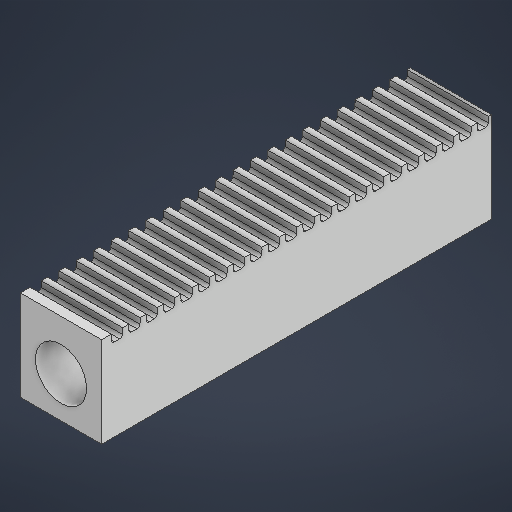
# Autodesk Inventor part: Servo gear pin
Saved by Autodesk Inventor 2027 (Build 310192060, 192F)
## iProperties
Created: 2026-10-23
Part Number: Servo gear pin
Material: Generic
Document SubType Name: Modeling
Designer: troop
Density: 1 g/cm^3
Appearance: Default
Author: troop
Autodesk Inventor part; units mm, degrees
ref_plane "YZ Plane" through (0, 0, 0) normal (1, 0, 0) x (0, 1, 0)
ref_plane "XZ Plane" through (0, 0, 0) normal (0, 1, 0) x (-1, 0, 0)
ref_plane "XY Plane" through (0, 0, 0) normal (0, 0, 1) x (1, 0, 0)
sketch "Sketch1" plane through (0, 0, 0) normal (0, 0, 1) x (1, 0, 0)
  line L0 (0, 0) -> (7.9375, 0)
  line L1 (7.9375, 0) -> (7.9375, 7.9375)
  line L2 (7.9375, 7.9375) -> (0, 7.9375)
  line L3 (0, 7.9375) -> (0, 0)
  dimension "d0" = 7.9375
  dimension "d1" = 7.9375
  constraints: 8 end point, 2 parallel, 1 horizontal, 1 perpendicular
  measures "d0" distance of L2.end L1.end
  measures "d1" distance between parallel lines of L0 L2
extrude "Extrusion1" add sketch "Sketch1" along normal blind 38.1
sketch "Sketch2" plane through (0, 0, 38.1) normal (0, 0, 1) x (1, 0, 0)
  circle A0 centre (3.9688, 3.9688) radius 2.5
  point P0 (0, 0)
  dimension "d4" = 5
  dimension "d5" = 3.9688
  dimension "d6" = 3.9688
  constraints: 1 centre point
  measures "d4" diameter of A0
  measures "d5" horizontal distance of point (0, 0) A0.centre
  measures "d6" horizontal distance of point (0, 0) A0.centre
extrude "Extrusion2" cut sketch "Sketch2" against normal blind 25.4
sketch "Sketch3" plane through (7.9375, 0, 0) normal (1, 0, 0) x (0, 0, -1)
  line L0 (0, 7.9375) -> (-38.1, 7.9375) projected
  line L1 (0, 7.9375) -> (0, 8.8375)
  line L2 (0, 8.8375) -> (-0.3048, 8.8375)
  line L3 (-1.347, 8.0375) -> (-0.347, 8.0375)
  arc A0 (-0.347, 8.0375) -> (-0.3048, 8.8375) centre (-3.3369, 8.5963) ccw
  arc A1 (-1.3978, 8.8375) -> (-1.347, 8.0375) centre (1.6367, 8.6286) ccw
  line L4 (-1.3978, 8.8375) -> (-1.7026, 8.8375)
  line L5 (-1.7026, 8.8375) -> (-1.7026, 7.9375)
  line L6 (-3.4052, 7.9375) -> (-3.4052, 8.8375)
  line L7 (-3.4052, 8.8375) -> (-3.1004, 8.8375)
  line L8 (-2.0582, 8.0375) -> (-3.0582, 8.0375)
  arc A2 (-3.1004, 8.8375) -> (-3.0582, 8.0375) centre (-0.0683, 8.5963) ccw
  arc A3 (-2.0582, 8.0375) -> (-2.0074, 8.8375) centre (-5.0419, 8.6286) ccw
  line L9 (-2.0074, 8.8375) -> (-1.7026, 8.8375)
  line L10 (-6.8104, 7.9375) -> (-6.8104, 8.8375)
  line L11 (-6.8104, 8.8375) -> (-6.5056, 8.8375)
  line L12 (-5.4634, 8.0375) -> (-6.4634, 8.0375)
  arc A4 (-6.5056, 8.8375) -> (-6.4634, 8.0375) centre (-3.4735, 8.5963) ccw
  arc A5 (-5.4634, 8.0375) -> (-5.4126, 8.8375) centre (-8.4471, 8.6286) ccw
  line L13 (-5.4126, 8.8375) -> (-5.1078, 8.8375)
  line L14 (-5.1078, 8.8375) -> (-5.1078, 7.9375)
  line L15 (-3.4052, 8.8375) -> (-3.71, 8.8375)
  line L16 (-4.7522, 8.0375) -> (-3.7522, 8.0375)
  arc A6 (-3.7522, 8.0375) -> (-3.71, 8.8375) centre (-6.7421, 8.5963) ccw
  arc A7 (-4.803, 8.8375) -> (-4.7522, 8.0375) centre (-1.7685, 8.6286) ccw
  line L17 (-4.803, 8.8375) -> (-5.1078, 8.8375)
  line L18 (-13.6207, 7.9375) -> (-13.6207, 8.8375)
  line L19 (-13.6207, 8.8375) -> (-13.3159, 8.8375)
  line L20 (-12.2738, 8.0375) -> (-13.2738, 8.0375)
  arc A8 (-13.3159, 8.8375) -> (-13.2738, 8.0375) centre (-10.2838, 8.5963) ccw
  arc A9 (-12.2738, 8.0375) -> (-12.223, 8.8375) centre (-15.2575, 8.6286) ccw
  line L21 (-12.223, 8.8375) -> (-11.9182, 8.8375)
  line L22 (-11.9182, 8.8375) -> (-11.9182, 7.9375)
  line L23 (-10.2156, 7.9375) -> (-10.2156, 8.8375)
  line L24 (-10.2156, 8.8375) -> (-10.5204, 8.8375)
  line L25 (-11.5626, 8.0375) -> (-10.5626, 8.0375)
  arc A10 (-10.5626, 8.0375) -> (-10.5204, 8.8375) centre (-13.5525, 8.5963) ccw
  arc A11 (-11.6134, 8.8375) -> (-11.5626, 8.0375) centre (-8.5789, 8.6286) ccw
  line L26 (-11.6134, 8.8375) -> (-11.9182, 8.8375)
  line L27 (-8.2082, 8.8375) -> (-8.513, 8.8375)
  arc A12 (-8.2082, 8.8375) -> (-8.1574, 8.0375) centre (-5.1737, 8.6286) ccw
  line L28 (-8.1574, 8.0375) -> (-7.1574, 8.0375)
  arc A13 (-7.1574, 8.0375) -> (-7.1152, 8.8375) centre (-10.1473, 8.5963) ccw
  line L29 (-6.8104, 8.8375) -> (-7.1152, 8.8375)
  line L30 (-8.513, 8.8375) -> (-8.513, 7.9375)
  arc A14 (-8.8686, 8.0375) -> (-8.8178, 8.8375) centre (-11.8523, 8.6286) ccw
  line L31 (-8.8686, 8.0375) -> (-9.8686, 8.0375)
  arc A15 (-9.9108, 8.8375) -> (-9.8686, 8.0375) centre (-6.8787, 8.5963) ccw
  line L32 (-10.2156, 8.8375) -> (-9.9108, 8.8375)
  line L33 (-8.8178, 8.8375) -> (-8.513, 8.8375)
  line L34 (-27.2415, 7.9375) -> (-27.2415, 8.8375)
  line L35 (-27.2415, 8.8375) -> (-26.9367, 8.8375)
  line L36 (-25.8945, 8.0375) -> (-26.8945, 8.0375)
  arc A16 (-26.9367, 8.8375) -> (-26.8945, 8.0375) centre (-23.9046, 8.5963) ccw
  arc A17 (-25.8945, 8.0375) -> (-25.8437, 8.8375) centre (-28.8782, 8.6286) ccw
  line L37 (-25.8437, 8.8375) -> (-25.5389, 8.8375)
  line L38 (-25.5389, 8.8375) -> (-25.5389, 7.9375)
  line L39 (-23.8363, 7.9375) -> (-23.8363, 8.8375)
  line L40 (-23.8363, 8.8375) -> (-24.1411, 8.8375)
  line L41 (-25.1833, 8.0375) -> (-24.1833, 8.0375)
  arc A18 (-24.1833, 8.0375) -> (-24.1411, 8.8375) centre (-27.1732, 8.5963) ccw
  arc A19 (-25.2341, 8.8375) -> (-25.1833, 8.0375) centre (-22.1996, 8.6286) ccw
  line L42 (-25.2341, 8.8375) -> (-25.5389, 8.8375)
  line L43 (-21.8289, 8.8375) -> (-22.1337, 8.8375)
  arc A20 (-21.8289, 8.8375) -> (-21.7781, 8.0375) centre (-18.7944, 8.6286) ccw
  line L44 (-21.7781, 8.0375) -> (-20.7781, 8.0375)
  arc A21 (-20.7781, 8.0375) -> (-20.7359, 8.8375) centre (-23.768, 8.5963) ccw
  line L45 (-20.4311, 8.8375) -> (-20.7359, 8.8375)
  line L46 (-20.4311, 7.9375) -> (-20.4311, 8.8375)
  line L47 (-22.1337, 8.8375) -> (-22.1337, 7.9375)
  arc A22 (-22.4893, 8.0375) -> (-22.4385, 8.8375) centre (-25.473, 8.6286) ccw
  line L48 (-22.4893, 8.0375) -> (-23.4893, 8.0375)
  arc A23 (-23.5315, 8.8375) -> (-23.4893, 8.0375) centre (-20.4994, 8.5963) ccw
  line L49 (-23.8363, 8.8375) -> (-23.5315, 8.8375)
  line L50 (-22.4385, 8.8375) -> (-22.1337, 8.8375)
  line L51 (-13.6207, 8.8375) -> (-13.9255, 8.8375)
  line L52 (-14.9677, 8.0375) -> (-13.9677, 8.0375)
  arc A24 (-13.9677, 8.0375) -> (-13.9255, 8.8375) centre (-16.9577, 8.5963) ccw
  arc A25 (-15.0185, 8.8375) -> (-14.9677, 8.0375) centre (-11.984, 8.6286) ccw
  line L53 (-15.6789, 8.0375) -> (-16.6789, 8.0375)
  arc A26 (-15.6789, 8.0375) -> (-15.6281, 8.8375) centre (-18.6626, 8.6286) ccw
  line L54 (-15.6281, 8.8375) -> (-15.3233, 8.8375)
  line L55 (-15.0185, 8.8375) -> (-15.3233, 8.8375)
  line L56 (-15.3233, 8.8375) -> (-15.3233, 7.9375)
  arc A27 (-16.7211, 8.8375) -> (-16.6789, 8.0375) centre (-13.689, 8.5963) ccw
  line L57 (-17.0259, 8.8375) -> (-16.7211, 8.8375)
  line L58 (-17.0259, 7.9375) -> (-17.0259, 8.8375)
  line L59 (-17.0259, 8.8375) -> (-17.3307, 8.8375)
  arc A28 (-17.3729, 8.0375) -> (-17.3307, 8.8375) centre (-20.3628, 8.5963) ccw
  line L60 (-18.3729, 8.0375) -> (-17.3729, 8.0375)
  line L61 (-18.7285, 8.8375) -> (-18.7285, 7.9375)
  line L62 (-18.4237, 8.8375) -> (-18.7285, 8.8375)
  line L63 (-19.0333, 8.8375) -> (-18.7285, 8.8375)
  arc A29 (-18.4237, 8.8375) -> (-18.3729, 8.0375) centre (-15.3892, 8.6286) ccw
  arc A30 (-19.0841, 8.0375) -> (-19.0333, 8.8375) centre (-22.0678, 8.6286) ccw
  line L64 (-19.0841, 8.0375) -> (-20.0841, 8.0375)
  arc A31 (-20.1263, 8.8375) -> (-20.0841, 8.0375) centre (-17.0942, 8.5963) ccw
  line L65 (-20.4311, 8.8375) -> (-20.1263, 8.8375)
  line L66 (-27.2415, 8.8375) -> (-27.5463, 8.8375)
  line L67 (-28.5885, 8.0375) -> (-27.5885, 8.0375)
  line L68 (-35.3989, 8.0375) -> (-34.3989, 8.0375)
  arc A32 (-35.4497, 8.8375) -> (-35.3989, 8.0375) centre (-32.4152, 8.6286) ccw
  line L69 (-35.4497, 8.8375) -> (-35.7545, 8.8375)
  line L70 (-35.7545, 8.8375) -> (-35.7545, 7.9375)
  line L71 (-36.0593, 8.8375) -> (-35.7545, 8.8375)
  arc A33 (-36.1101, 8.0375) -> (-36.0593, 8.8375) centre (-39.0938, 8.6286) ccw
  line L72 (-36.1101, 8.0375) -> (-37.1101, 8.0375)
  line L73 (-30.6467, 7.9375) -> (-30.6467, 8.8375)
  line L74 (-30.6467, 8.8375) -> (-30.3419, 8.8375)
  arc A34 (-30.3419, 8.8375) -> (-30.2997, 8.0375) centre (-27.3098, 8.5963) ccw
  line L75 (-29.2997, 8.0375) -> (-30.2997, 8.0375)
  line L76 (-28.9441, 8.8375) -> (-28.9441, 7.9375)
  line L77 (-28.6393, 8.8375) -> (-28.9441, 8.8375)
  arc A35 (-28.6393, 8.8375) -> (-28.5885, 8.0375) centre (-25.6048, 8.6286) ccw
  arc A36 (-27.5885, 8.0375) -> (-27.5463, 8.8375) centre (-30.5784, 8.5963) ccw
  arc A37 (-34.3989, 8.0375) -> (-34.3567, 8.8375) centre (-37.3888, 8.5963) ccw
  line L78 (-34.0519, 8.8375) -> (-34.3567, 8.8375)
  line L79 (-34.0519, 8.8375) -> (-33.7471, 8.8375)
  arc A38 (-33.7471, 8.8375) -> (-33.7049, 8.0375) centre (-30.715, 8.5963) ccw
  line L80 (-32.7049, 8.0375) -> (-33.7049, 8.0375)
  arc A39 (-32.7049, 8.0375) -> (-32.6541, 8.8375) centre (-35.6886, 8.6286) ccw
  line L81 (-32.6541, 8.8375) -> (-32.3493, 8.8375)
  arc A40 (-29.2997, 8.0375) -> (-29.2489, 8.8375) centre (-32.2834, 8.6286) ccw
  line L82 (-29.2489, 8.8375) -> (-28.9441, 8.8375)
  line L83 (-32.3493, 8.8375) -> (-32.3493, 7.9375)
  line L84 (-32.0445, 8.8375) -> (-32.3493, 8.8375)
  arc A41 (-32.0445, 8.8375) -> (-31.9937, 8.0375) centre (-29.01, 8.6286) ccw
  line L85 (-31.9937, 8.0375) -> (-30.9937, 8.0375)
  arc A42 (-30.9937, 8.0375) -> (-30.9515, 8.8375) centre (-33.9836, 8.5963) ccw
  line L86 (-30.6467, 8.8375) -> (-30.9515, 8.8375)
  line L87 (-34.0519, 7.9375) -> (-34.0519, 8.8375)
  line L88 (-37.4571, 8.8375) -> (-37.1523, 8.8375)
  arc A43 (-37.1523, 8.8375) -> (-37.1101, 8.0375) centre (-34.1201, 8.5963) ccw
  line L89 (-37.4571, 7.9375) -> (-37.4571, 8.8375)
  line L90 (-37.4571, 8.8375) -> (-37.7619, 8.8375)
  line L91 (-38.1, 0) -> (-38.1, 7.9375) projected
  line L92 (-38.1, 7.9375) -> (-38.1, 8.8375)
  line L93 (-38.1, 8.8375) -> (-37.7619, 8.8375)
  point P0 (0, 0)
  dimension "d9" = 0.9
  dimension "d10" = 0.3048
  dimension "d11" = 1
  dimension "d13" = 0.1
  dimension "d15" = 3.0417
  dimension "d16" = 3.0417
  dimension "d19" = 0.3048
  dimension "d20" = 0.9
  dimension "d27" = 1.7026
  dimension "d29" = 0.0508
  constraints: 184 end point, 169 symmetric about line, 88 point on circle, 44 centre point, 3 horizontal, 3 vertical, 1 perpendicular, 44 other
  measures "d9" distance of L1.start L1.end
  measures "d10" distance of L1.end L2.end
  measures "d11" distance of L3.start L3.end
  measures "d15" radius of A0
  measures "d16" radius of A1
  measures "d19" distance of L4.start L4.end
  measures "d27" distance between parallel lines of L1 L5
  measures "d29" horizontal distance of L3.start L4.start
extrude "Extrusion3" add sketch "Sketch3" against normal blind 7.9375
fillet "Fillet1" radius 0.2794 44 edges at (3.9687, 8.0375, 37.1101) (3.9687, 8.0375, 35.3989) (3.9687, 8.0375, 33.7049) (3.9687, 8.0375, 31.9937) (3.9687, 8.0375, 30.2997) (3.9687, 8.0375, 28.5885) (3.9687, 8.0375, 26.8945) (3.9687, 8.0375, 25.1833) (3.9687, 8.0375, 23.4893) (3.9687, 8.0375, 21.7781) (3.9687, 8.0375, 20.0841) (3.9687, 8.0375, 18.3729) (3.9687, 8.0375, 16.6789) (3.9687, 8.0375, 14.9677) (3.9687, 8.0375, 13.2738) (3.9687, 8.0375, 11.5626) (3.9687, 8.0375, 9.8686) (3.9687, 8.0375, 8.1574) (3.9687, 8.0375, 6.4634) (3.9687, 8.0375, 4.7522) (3.9687, 8.0375, 3.0582) (3.9687, 8.0375, 1.347) (3.9687, 8.0375, 0.347) (3.9687, 8.0375, 2.0582) (3.9687, 8.0375, 3.7522) (3.9687, 8.0375, 5.4634) (3.9687, 8.0375, 7.1574) (3.9687, 8.0375, 8.8686) (3.9687, 8.0375, 10.5626) (3.9687, 8.0375, 12.2738) (3.9687, 8.0375, 13.9677) (3.9687, 8.0375, 15.6789) (3.9687, 8.0375, 17.3729) (3.9687, 8.0375, 19.0841) (3.9687, 8.0375, 20.7781) (3.9687, 8.0375, 22.4893) (3.9687, 8.0375, 24.1833) (3.9687, 8.0375, 25.8945) (3.9687, 8.0375, 27.5885) (3.9687, 8.0375, 29.2997) (3.9687, 8.0375, 30.9937) (3.9687, 8.0375, 32.7049) (3.9687, 8.0375, 34.3989) (3.9687, 8.0375, 36.1101)
body "Solid1"
